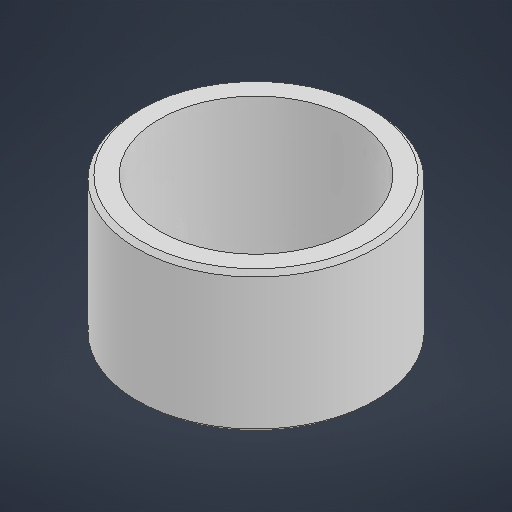
# Autodesk Inventor part: distanceTube_armshaft
Saved by Autodesk Inventor 2027.1 (Build 311270010, 270A)
## iProperties
Created: 2026-10-10
Part Number: distanceTube_armshaft
Material: Generic
Document SubType Name: Modeling
Designer: lucao
Density: 0.855495 g/cm^3
Appearance: Default
Mass: 2.91 g
Surface Area: 29.9605 cm^2
Volume: 3.40154 cm^3
Author: lucao
## iProperties of the stored document distanceTube_armshaft_3DPrint.ipt
Created: 2026-10-13
Part Number: distanceTube_armshaft_3DPrint
Material: Generic
Document SubType Name: Modeling
Designer: lucao
Density: 1 g/cm^3
Appearance: Default
Author: lucao
Autodesk Inventor part; units mm, degrees
ref_plane "YZ Plane" through (0, 0, 0) normal (1, 0, 0) x (0, 1, 0)
ref_plane "XZ Plane" through (0, 0, 0) normal (0, 1, 0) x (-1, 0, 0)
ref_plane "XY Plane" through (0, 0, 0) normal (0, 0, 1) x (1, 0, 0)
sketch "Sketch1" plane through (0, 0, 0) normal (0, 1, 0) x (-1, 0, 0)
  circle A0 centre (0, 0) radius 14
  circle A1 centre (0, 0) radius 11.4
  dimension "d0" = 28
  dimension "d1" = 22.8
  constraints: 2 centre point, 2 coincident
  measures "d0" diameter of A0
  measures "d1" diameter of A1
extrude "Extrusion1" add sketch "Sketch1" along normal blind 16.5
chamfer "Chamfer1" distance 0.5 angle 45 2 edges at (14, 16.5, 0) (14, 0, 0)
body "Solid1"
